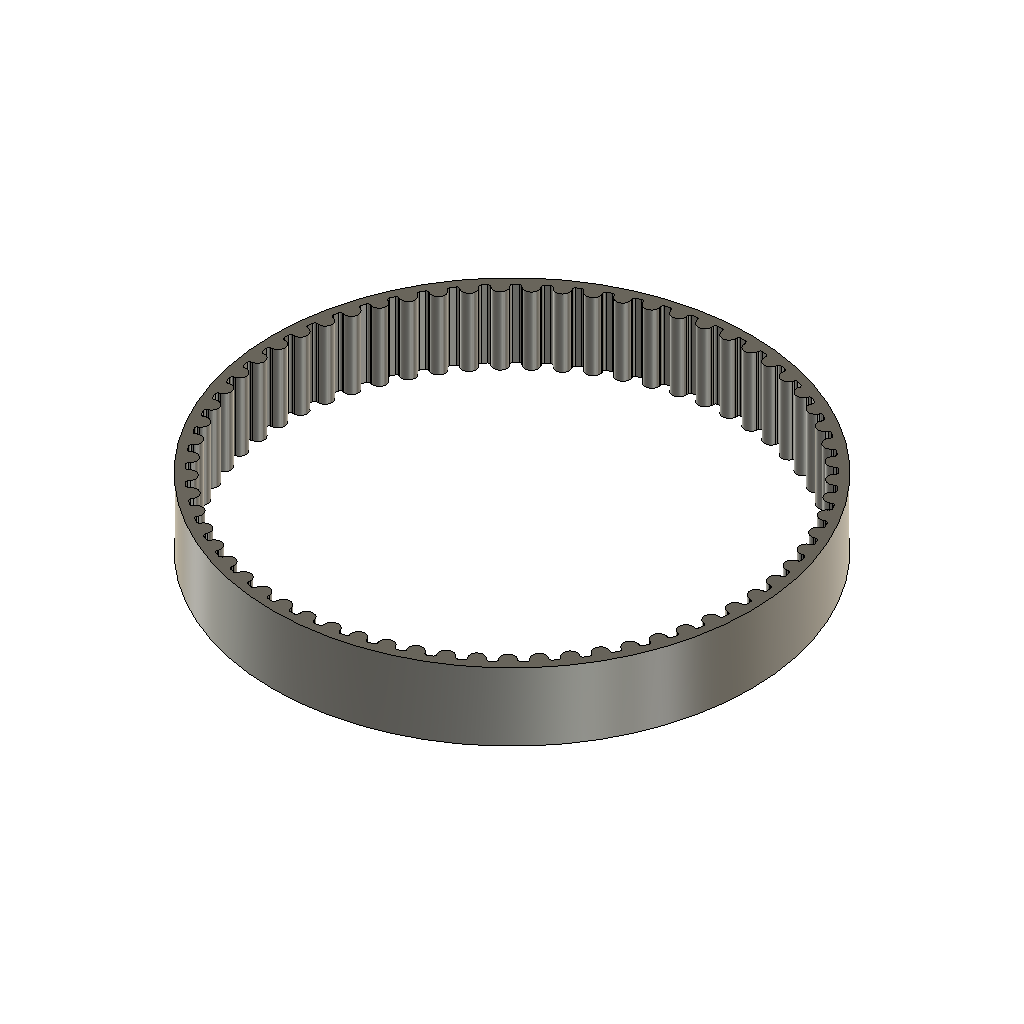
HTD-5M Belt Print (Autodesk Fusion 360 design; units mm, degrees)
Autodesk Fusion 360 part; units mm, degrees
sketch "Teeth" plane through (0, 0, 0) normal (0, 0, 1) x (1, 0, 0)
  circle A0 centre (0, 0) radius 51.7254
  arc A1 (0.5042, 51.1509) -> (0, 51.1534) centre (0, 0) ccw
  arc A2 (0.9284, 50.7577) -> (0.5042, 51.1509) centre (0.4999, 50.7209) ccw
  line L0 (0.9284, 50.7577) -> (0.9593, 50.397)
  arc A3 (0.9593, 50.397) -> (2.3719, 49.0361) centre (2.4439, 50.5243) ccw
  line L1 (0, 0) -> (0, 51.1534) construction
  line L2 (0, 0) -> (2.4439, 50.5243) construction
  line L3 (0, 51.1534) -> (0, 51.7254)
  arc A4 (2.499, 51.665) -> (0, 51.7254) centre (0, 0) ccw
  arc A5 (2.3719, 49.0361) -> (3.9092, 50.2543) centre (2.4439, 50.5243) ccw
  line L4 (3.9748, 50.6103) -> (3.9092, 50.2543)
  arc A6 (4.435, 50.9608) -> (3.9748, 50.6103) centre (4.3977, 50.5324) ccw
  arc A7 (4.937, 50.9146) -> (4.435, 50.9608) centre (0, 0) ccw
  line L5 (4.937, 50.9146) -> (4.9922, 51.4839)
  arc A8 (4.9922, 51.4839) -> (2.499, 51.665) centre (0, 0) ccw
  line L6 (0.9284, 50.7577) -> (2.4516, 50.684) construction
  line L7 (2.4516, 50.684) -> (2.4439, 50.5243) construction
  circle A9 centre (0, 0) radius 52.8934
  dimension "d50" = 103.4508
  dimension "d57" = 0.43
  dimension "d58" = 1.49
  dimension "d59" = 2.769
  dimension "d62" = 2.632
  dimension "d65" = 0.572
  dimension "d67" = 1.525
  dimension "d68" = 105.7868
  constraint tangent A1 A2
  constraint coincident A0.centre A1.centre
  constraint vertical A0.centre A1.end
  constraint coincident A0 L3.end
  constraint parallel L1 L3
  constraint coincident A0 A4.start
  constraint collinear A3.centre A0.centre A4.start
  constraint coincident A3.centre L2.end
  constraint coincident L2 A3.end
  constraint symmetric L0.end L2 A5.end
  constraint symmetric A2.start L2 L4.start
  constraint symmetric A1.start L2 A6.start
  constraint symmetric A1 L2 A7
  constraint symmetric A2 L2 A6
  constraint symmetric A3 L2 A5
  constraint symmetric L2 A1.end A7.start
  constraint symmetric L2 L3.end L5.end
  constraint symmetric L2 A4.start A8.end
  constraint symmetric L2 A4 A8
  constraint symmetric L2 A3.end A5.start
  constraint tangent L0 A3
  constraint tangent A2 L0
  constraint perpendicular L2 L6
  constraint parallel L2 L7
  constraint concentric A0 A9
  measures "d50" diameter of A0
  measures "d57" radius of A2
  measures "d58" radius of A3
  measures "d59" angle of L1 L2
  measures "d62" distance of A4.start A3.end
  measures "d65" distance of A1.end L3.end
  measures "d67" distance of A2.start L6.end
  measures "d68" diameter of A9
extrude "Extrude1" add sketch "Teeth" along normal mid plane 15
extrude "Extrude3" add sketch "Teeth" along normal through all of body 1 and the other way through all of body 1 contours A0 A1 A2 L0 A3 L3 A4 A5 L4 A6 A7 L5 A8
pattern_circular "C-Pattern1" count 65 over 360 about axis through (0, 0, 0) along (0, 0, 1) of "Extrude3"
equation "p = 5 mm"
equation "n = 65" comment "Number of Teeth"
equation "PD = n * p / 3.14159"
equation "d25 = width"
equation "d50 = PD"
equation "d52 = n"
equation "d59 = ( 180 / n ) * 1 deg"
equation "width = 15 mm"
equation "d67 = 3.05 mm / 2"
equation "d68 = d50 + 2 * 1.168 mm"
